Autodesk Fusion 360 part; units mm, degrees
(part 3 of 3)
  spline S132 degree 3 poles (44.3046, -6.0249) (44.0782, -5.7263) (43.6074, -5.1055) (43.5551, -4.3265) (43.528, -3.9222) knots 0 0 0 0 0.109936 0.228563 0.228563 0.228563 0.228563
  spline S133 degree 3 poles (43.528, -3.9222) (43.5425, -3.6461) (43.5714, -3.0995) (43.7867, -2.5965) (43.8932, -2.3475) knots 0 0 0 0 0.082236 0.16278 0.16278 0.16278 0.16278
  spline S134 degree 3 poles (43.8932, -2.3475) (44.0238, -2.1208) (44.2792, -1.6775) (44.6942, -1.3791) (44.897, -1.2333) knots 0 0 0 0 0.077495 0.151511 0.151511 0.151511 0.151511
  spline S135 degree 3 poles (44.897, -1.2333) (45.1198, -1.1205) (45.5753, -0.8899) (46.0853, -0.8612) (46.3458, -0.8465) knots 0 0 0 0 0.074062 0.151408 0.151408 0.151408 0.151408
  spline S136 degree 3 poles (46.3458, -0.8465) (46.7837, -0.8873) (47.6516, -0.9682) (48.2851, -1.5662) (48.5989, -1.8626) knots 0 0 0 0 0.127939 0.253596 0.253596 0.253596 0.253596
  spline S137 degree 3 poles (48.5989, -1.8626) (48.8518, -2.3009) (49.4454, -3.3299) (49.4615, -4.5253) (49.4707, -5.2115) knots 0 0 0 0 0.149571 0.35112 0.35112 0.35112 0.35112
  spline S138 degree 3 poles (49.4707, -5.2115) (49.459, -5.9817) (49.4386, -7.3304) (48.7865, -8.5026) (48.5068, -9.0055) knots 0 0 0 0 0.226592 0.396798 0.396798 0.396798 0.396798
  spline S139 degree 3 poles (48.5068, -9.0055) (48.1977, -9.3062) (47.5669, -9.9199) (46.689, -9.9973) (46.2415, -10.0368) knots 0 0 0 0 0.12539 0.255812 0.255812 0.255812 0.255812
  spline S140 degree 3 poles (53.719, -0.8465) (54.049, -0.866) (54.6793, -0.9032) (55.1973, -1.2619) (55.4441, -1.4328) knots 0 0 0 0 0.097038 0.185349 0.185349 0.185349 0.185349
  spline S141 degree 3 poles (55.4441, -1.4328) (55.6458, -1.6563) (56.0709, -2.1273) (56.1872, -2.7526) (56.2483, -3.0812) knots 0 0 0 0 0.088559 0.186622 0.186622 0.186622 0.186622
  line L73 (56.2483, -3.0812) -> (55.1862, -3.1794)
  spline S142 degree 3 poles (55.1862, -3.1794) (55.1392, -2.9549) (55.0543, -2.5494) (54.7889, -2.2336) (54.6705, -2.0928) knots 0 0 0 0 0.067535 0.121935 0.121935 0.121935 0.121935
  spline S143 degree 3 poles (54.6705, -2.0928) (54.5307, -1.9943) (54.2385, -1.7886) (53.8809, -1.7666) (53.6944, -1.7551) knots 0 0 0 0 0.050278 0.10511 0.10511 0.10511 0.10511
  spline S144 degree 3 poles (53.6944, -1.7551) (53.5321, -1.7635) (53.218, -1.7796) (52.937, -1.9204) (52.8012, -1.9884) knots 0 0 0 0 0.048163 0.093215 0.093215 0.093215 0.093215
  spline S145 degree 3 poles (52.8012, -1.9884) (52.6787, -2.0731) (52.4323, -2.2437) (52.2591, -2.4884) (52.1719, -2.6115) knots 0 0 0 0 0.044287 0.089169 0.089169 0.089169 0.089169
  spline S146 degree 3 poles (52.1719, -2.6115) (52.0912, -2.762) (51.912, -3.0962) (51.8143, -3.4629) (51.7606, -3.6644) knots 0 0 0 0 0.051067 0.113373 0.113373 0.113373 0.113373
  spline S147 degree 3 poles (51.7606, -3.6644) (51.7122, -3.8866) (51.6154, -4.3317) (51.6017, -4.787) (51.5948, -5.015) knots 0 0 0 0 0.068062 0.136332 0.136332 0.136332 0.136332
  spline S148 degree 3 poles (51.5948, -5.015) (51.5952, -5.0457) (51.5961, -5.1194) (51.5992, -5.193) (51.601, -5.236) knots 0 0 0 0 0.00921 0.02211 0.02211 0.02211 0.02211
  spline S149 degree 3 poles (51.601, -5.236) (51.723, -5.0675) (51.9709, -4.7253) (52.3261, -4.496) (52.5065, -4.3796) knots 0 0 0 0 0.061834 0.125606 0.125606 0.125606 0.125606
  spline S150 degree 3 poles (52.5065, -4.3796) (52.7021, -4.2838) (53.0946, -4.0916) (53.5309, -4.0647) (53.7497, -4.0512) knots 0 0 0 0 0.064656 0.129715 0.129715 0.129715 0.129715
  spline S151 degree 3 poles (53.7497, -4.0512) (54.1079, -4.085) (54.8248, -4.1528) (55.3685, -4.6252) (55.6405, -4.8615) knots 0 0 0 0 0.105109 0.210375 0.210375 0.210375 0.210375
  spline S152 degree 3 poles (55.6405, -4.8615) (55.866, -5.1627) (56.3391, -5.7946) (56.3883, -6.5845) (56.4141, -6.998) knots 0 0 0 0 0.110401 0.231667 0.231667 0.231667 0.231667
  spline S153 degree 3 poles (56.4141, -6.998) (56.387, -7.425) (56.3353, -8.2415) (55.8421, -8.8917) (55.6068, -9.2019) knots 0 0 0 0 0.125188 0.239403 0.239403 0.239403 0.239403
  spline S154 degree 3 poles (55.6068, -9.2019) (55.3181, -9.4454) (54.7333, -9.9388) (53.9703, -10.0039) (53.5839, -10.0368) knots 0 0 0 0 0.110411 0.223699 0.223699 0.223699 0.223699
  spline S155 degree 3 poles (53.5839, -10.0368) (53.2979, -10.0174) (52.7278, -9.9786) (52.2277, -9.702) (51.9785, -9.5641) knots 0 0 0 0 0.084857 0.169181 0.169181 0.169181 0.169181
  spline S156 degree 3 poles (51.9785, -9.5641) (51.7491, -9.3863) (51.2786, -9.0216) (51.0107, -8.4893) (50.8735, -8.2166) knots 0 0 0 0 0.08592 0.176242 0.176242 0.176242 0.176242
  spline S157 degree 3 poles (50.8735, -8.2166) (50.7639, -7.8622) (50.5093, -7.0391) (50.5008, -6.1758) (50.4959, -5.6842) knots 0 0 0 0 0.110733 0.257226 0.257226 0.257226 0.257226
  spline S158 degree 3 poles (50.4959, -5.6842) (50.5029, -5.1642) (50.5154, -4.232) (50.7615, -3.334) (50.8704, -2.9369) knots 0 0 0 0 0.155219 0.278258 0.278258 0.278258 0.278258
  spline S159 degree 3 poles (50.8704, -2.9369) (51.0041, -2.6212) (51.2596, -2.0182) (51.7507, -1.5864) (51.9847, -1.3806) knots 0 0 0 0 0.101354 0.193602 0.193602 0.193602 0.193602
  spline S160 degree 3 poles (51.9847, -1.3806) (52.2455, -1.2249) (52.7797, -0.906) (53.4011, -0.8666) (53.719, -0.8465) knots 0 0 0 0 0.089778 0.183816 0.183816 0.183816 0.183816
  spline S161 degree 3 poles (61.5464, -2.6606) (61.6352, -2.5633) (61.8062, -2.3758) (61.9458, -2.164) (62.013, -2.0621) knots 0 0 0 0 0.039446 0.075997 0.075997 0.075997 0.075997
  line L74 (62.013, -2.0621) -> (57.5989, -2.0621)
  line L75 (57.5989, -2.0621) -> (57.5989, -1)
  line L76 (57.5989, -1) -> (63.5477, -1)
  spline S162 degree 3 poles (63.5477, -1) (63.5455, -1.1315) (63.5411, -1.3938) (63.4595, -1.6431) (63.4188, -1.7674) knots 0 0 0 0 0.039224 0.078207 0.078207 0.078207 0.078207
  spline S163 degree 3 poles (63.4188, -1.7674) (63.3283, -1.9732) (63.1387, -2.4042) (62.8448, -2.7723) (62.6913, -2.9645) knots 0 0 0 0 0.067164 0.140612 0.140612 0.140612 0.140612
  spline S164 degree 3 poles (62.6913, -2.9645) (62.4914, -3.1804) (62.0405, -3.6673) (61.5298, -4.0914) (61.2456, -4.3274) knots 0 0 0 0 0.088193 0.198876 0.198876 0.198876 0.198876
  spline S165 degree 3 poles (61.2456, -4.3274) (60.823, -4.6738) (60.1112, -5.2575) (59.5078, -5.9515) (59.2626, -6.2336) knots 0 0 0 0 0.163519 0.275478 0.275478 0.275478 0.275478
  spline S166 degree 3 poles (59.2626, -6.2336) (59.1126, -6.4537) (58.8368, -6.8581) (58.7751, -7.3421) (58.7469, -7.5628) knots 0 0 0 0 0.078556 0.144369 0.144369 0.144369 0.144369
  spline S167 degree 3 poles (58.7469, -7.5628) (58.7663, -7.773) (58.805, -8.1924) (59.0796, -8.5116) (59.2166, -8.6709) knots 0 0 0 0 0.061675 0.123053 0.123053 0.123053 0.123053
  spline S168 degree 3 poles (59.2166, -8.6709) (59.3898, -8.8024) (59.7512, -9.0768) (60.2051, -9.1066) (60.4413, -9.1221) knots 0 0 0 0 0.063814 0.133113 0.133113 0.133113 0.133113
  spline S169 degree 3 poles (60.4413, -9.1221) (60.69, -9.1061) (61.1654, -9.0755) (61.5397, -8.7828) (61.7183, -8.6432) knots 0 0 0 0 0.072819 0.139233 0.139233 0.139233 0.139233
  spline S170 degree 3 poles (61.7183, -8.6432) (61.8581, -8.4604) (62.1564, -8.0703) (62.187, -7.5785) (62.2033, -7.3172) knots 0 0 0 0 0.067532 0.14406 0.14406 0.14406 0.14406
  line L77 (62.2033, -7.3172) -> (63.339, -7.4338)
  spline S171 degree 3 poles (63.339, -7.4338) (63.2823, -7.8239) (63.1758, -8.5568) (62.6889, -9.1113) (62.4611, -9.3707) knots 0 0 0 0 0.115358 0.216751 0.216751 0.216751 0.216751
  spline S172 degree 3 poles (62.4611, -9.3707) (62.1732, -9.5648) (61.5573, -9.98) (60.8131, -10.0171) (60.4168, -10.0368) knots 0 0 0 0 0.102212 0.218671 0.218671 0.218671 0.218671
  spline S173 degree 3 poles (60.4168, -10.0368) (60.0162, -10.0148) (59.2608, -9.9733) (58.6522, -9.5278) (58.3663, -9.3186) knots 0 0 0 0 0.117411 0.221461 0.221461 0.221461 0.221461
  spline S174 degree 3 poles (58.3663, -9.3186) (58.1461, -9.0639) (57.7032, -8.5517) (57.642, -7.8773) (57.6112, -7.5382) knots 0 0 0 0 0.098363 0.197784 0.197784 0.197784 0.197784
  spline S175 degree 3 poles (57.6112, -7.5382) (57.6208, -7.3578) (57.6404, -6.9926) (57.7677, -6.6497) (57.8322, -6.4761) knots 0 0 0 0 0.053848 0.109039 0.109039 0.109039 0.109039
  spline S176 degree 3 poles (57.8322, -6.4761) (57.9239, -6.2934) (58.1227, -5.8971) (58.4106, -5.5593) (58.5658, -5.3772) knots 0 0 0 0 0.061098 0.132556 0.132556 0.132556 0.132556
  spline S177 degree 3 poles (58.5658, -5.3772) (58.7902, -5.1459) (59.3307, -4.5887) (59.9231, -4.0868) (60.2694, -3.7933) knots 0 0 0 0 0.096642 0.232736 0.232736 0.232736 0.232736
  spline S178 degree 3 poles (60.2694, -3.7933) (60.545, -3.5635) (60.9822, -3.1988) (61.3941, -2.8059) (61.5464, -2.6606) knots 0 0 0 0 0.10759 0.17073 0.17073 0.17073 0.17073
  line L78 (-45.6235, -2.0621) -> (-45.6235, -1)
  line L79 (-45.6235, -1) -> (-40, -1)
  line L80 (-40, -1) -> (-40, -10)
  line L81 (-40, -10) -> (-41.191, -10)
  line L82 (-41.191, -10) -> (-41.191, -2.0621)
  line L83 (-41.191, -2.0621) -> (-45.6235, -2.0621)
  line L84 (-69.1487, -8.0723) -> (-69.1487, -1)
  line L85 (-69.1487, -1) -> (-68.0068, -1)
  line L86 (-68.0068, -1) -> (-68.0068, -10)
  line L87 (-68.0068, -10) -> (-69.2285, -10)
  line L88 (-69.2285, -10) -> (-73.9557, -2.9338)
  line L89 (-73.9557, -2.9338) -> (-73.9557, -10)
  line L90 (-73.9557, -10) -> (-75.0975, -10)
  line L91 (-75.0975, -10) -> (-75.0975, -1)
  line L92 (-75.0975, -1) -> (-73.8759, -1)
  line L93 (-73.8759, -1) -> (-69.1487, -8.0723)
  spline S179 degree 3 poles (-60.5662, -3.603) (-60.5811, -3.8787) (-60.6096, -4.4061) (-60.8815, -4.8578) (-61.0113, -5.0733) knots 0 0 0 0 0.081417 0.155718 0.155718 0.155718 0.155718
  spline S180 degree 3 poles (-61.0113, -5.0733) (-61.1801, -5.2563) (-61.531, -5.6364) (-62.0235, -5.7972) (-62.279, -5.8806) knots 0 0 0 0 0.073422 0.152542 0.152542 0.152542 0.152542
  spline S181 degree 3 poles (-62.279, -5.8806) (-62.0689, -5.9678) (-61.6746, -6.1313) (-61.3919, -6.45) (-61.2599, -6.5989) knots 0 0 0 0 0.067199 0.126131 0.126131 0.126131 0.126131
  spline S182 degree 3 poles (-61.2599, -6.5989) (-61.1632, -6.7656) (-60.963, -7.1109) (-60.9402, -7.5099) (-60.9284, -7.7162) knots 0 0 0 0 0.056974 0.118009 0.118009 0.118009 0.118009
  spline S183 degree 3 poles (-60.9284, -7.7162) (-60.9575, -8.0303) (-61.0155, -8.6567) (-61.4285, -9.1311) (-61.6344, -9.3677) knots 0 0 0 0 0.092106 0.183705 0.183705 0.183705 0.183705
  spline S184 degree 3 poles (-61.6344, -9.3677) (-61.8984, -9.5627) (-62.4553, -9.9741) (-63.1484, -10.0152) (-63.513, -10.0368) knots 0 0 0 0 0.096365 0.203276 0.203276 0.203276 0.203276
  spline S185 degree 3 poles (-63.513, -10.0368) (-63.8803, -10.0142) (-64.5813, -9.971) (-65.1427, -9.5518) (-65.41, -9.3523) knots 0 0 0 0 0.107729 0.205612 0.205612 0.205612 0.205612
  spline S186 degree 3 poles (-65.41, -9.3523) (-65.6195, -9.1122) (-66.0373, -8.6334) (-66.098, -8.0009) (-66.1282, -7.6855) knots 0 0 0 0 0.093071 0.185613 0.185613 0.185613 0.185613
  spline S187 degree 3 poles (-66.1282, -7.6855) (-66.116, -7.4857) (-66.0923, -7.0963) (-65.8956, -6.7597) (-65.7998, -6.5958) knots 0 0 0 0 0.059125 0.115239 0.115239 0.115239 0.115239
  spline S188 degree 3 poles (-65.7998, -6.5958) (-65.67, -6.448) (-65.3935, -6.1329) (-65.0071, -5.9681) (-64.8022, -5.8806) knots 0 0 0 0 0.058279 0.124147 0.124147 0.124147 0.124147
  spline S189 degree 3 poles (-64.8022, -5.8806) (-65.0584, -5.7815) (-65.5496, -5.5915) (-65.8974, -5.1973) (-66.0638, -5.0089) knots 0 0 0 0 0.081068 0.15536 0.15536 0.15536 0.15536
  spline S190 degree 3 poles (-66.0638, -5.0089) (-66.19, -4.7944) (-66.4507, -4.3513) (-66.481, -3.8375) (-66.4966, -3.5723) knots 0 0 0 0 0.073547 0.151957 0.151957 0.151957 0.151957
  spline S191 degree 3 poles (-66.4966, -3.5723) (-66.4633, -3.2036) (-66.397, -2.47) (-65.9182, -1.9106) (-65.6801, -1.6323) knots 0 0 0 0 0.108151 0.215189 0.215189 0.215189 0.215189
  spline S192 degree 3 poles (-65.6801, -1.6323) (-65.3772, -1.4033) (-64.7429, -0.9235) (-63.9472, -0.8729) (-63.5314, -0.8465) knots 0 0 0 0 0.111408 0.233329 0.233329 0.233329 0.233329
  spline S193 degree 3 poles (-63.5314, -0.8465) (-63.1155, -0.8731) (-62.3193, -0.9241) (-61.6855, -1.4054) (-61.3827, -1.6354) knots 0 0 0 0 0.121933 0.233463 0.233463 0.233463 0.233463
  spline S194 degree 3 poles (-61.3827, -1.6354) (-61.1445, -1.9166) (-60.6632, -2.4851) (-60.5987, -3.2278) (-60.5662, -3.603) knots 0 0 0 0 0.107732 0.217767 0.217767 0.217767 0.217767
  spline S195 degree 3 poles (-56.281, -0.8465) (-55.951, -0.866) (-55.3207, -0.9032) (-54.8027, -1.2619) (-54.5559, -1.4328) knots 0 0 0 0 0.097038 0.185349 0.185349 0.185349 0.185349
  spline S196 degree 3 poles (-54.5559, -1.4328) (-54.3542, -1.6563) (-53.9291, -2.1273) (-53.8128, -2.7526) (-53.7517, -3.0812) knots 0 0 0 0 0.088559 0.186622 0.186622 0.186622 0.186622
  line L94 (-53.7517, -3.0812) -> (-54.8138, -3.1794)
  spline S197 degree 3 poles (-54.8138, -3.1794) (-54.8608, -2.9549) (-54.9457, -2.5494) (-55.2111, -2.2336) (-55.3295, -2.0928) knots 0 0 0 0 0.067535 0.121935 0.121935 0.121935 0.121935
  spline S198 degree 3 poles (-55.3295, -2.0928) (-55.4693, -1.9943) (-55.7615, -1.7886) (-56.1191, -1.7666) (-56.3056, -1.7551) knots 0 0 0 0 0.050278 0.10511 0.10511 0.10511 0.10511
  spline S199 degree 3 poles (-56.3056, -1.7551) (-56.4679, -1.7635) (-56.782, -1.7796) (-57.063, -1.9204) (-57.1988, -1.9884) knots 0 0 0 0 0.048163 0.093215 0.093215 0.093215 0.093215
  spline S200 degree 3 poles (-57.1988, -1.9884) (-57.3213, -2.0731) (-57.5677, -2.2437) (-57.7409, -2.4884) (-57.8281, -2.6115) knots 0 0 0 0 0.044287 0.089169 0.089169 0.089169 0.089169
  spline S201 degree 3 poles (-57.8281, -2.6115) (-57.9088, -2.762) (-58.088, -3.0962) (-58.1857, -3.4629) (-58.2394, -3.6644) knots 0 0 0 0 0.051067 0.113373 0.113373 0.113373 0.113373
  spline S202 degree 3 poles (-58.2394, -3.6644) (-58.2878, -3.8866) (-58.3846, -4.3317) (-58.3983, -4.787) (-58.4052, -5.015) knots 0 0 0 0 0.068062 0.136332 0.136332 0.136332 0.136332
  spline S203 degree 3 poles (-58.4052, -5.015) (-58.4048, -5.0457) (-58.4039, -5.1194) (-58.4008, -5.193) (-58.399, -5.236) knots 0 0 0 0 0.00921 0.02211 0.02211 0.02211 0.02211
  spline S204 degree 3 poles (-58.399, -5.236) (-58.277, -5.0675) (-58.0291, -4.7253) (-57.6739, -4.496) (-57.4935, -4.3796) knots 0 0 0 0 0.061834 0.125606 0.125606 0.125606 0.125606
  spline S205 degree 3 poles (-57.4935, -4.3796) (-57.2979, -4.2838) (-56.9054, -4.0916) (-56.4691, -4.0647) (-56.2503, -4.0512) knots 0 0 0 0 0.064656 0.129715 0.129715 0.129715 0.129715
  spline S206 degree 3 poles (-56.2503, -4.0512) (-55.8921, -4.085) (-55.1752, -4.1528) (-54.6315, -4.6252) (-54.3595, -4.8615) knots 0 0 0 0 0.105109 0.210375 0.210375 0.210375 0.210375
  spline S207 degree 3 poles (-54.3595, -4.8615) (-54.134, -5.1627) (-53.6609, -5.7946) (-53.6117, -6.5845) (-53.5859, -6.998) knots 0 0 0 0 0.110401 0.231667 0.231667 0.231667 0.231667
  spline S208 degree 3 poles (-53.5859, -6.998) (-53.613, -7.425) (-53.6647, -8.2415) (-54.1579, -8.8917) (-54.3932, -9.2019) knots 0 0 0 0 0.125188 0.239403 0.239403 0.239403 0.239403
  spline S209 degree 3 poles (-54.3932, -9.2019) (-54.6819, -9.4454) (-55.2667, -9.9388) (-56.0297, -10.0039) (-56.4161, -10.0368) knots 0 0 0 0 0.110411 0.223699 0.223699 0.223699 0.223699
  spline S210 degree 3 poles (-56.4161, -10.0368) (-56.7021, -10.0174) (-57.2722, -9.9786) (-57.7723, -9.702) (-58.0215, -9.5641) knots 0 0 0 0 0.084857 0.169181 0.169181 0.169181 0.169181
  spline S211 degree 3 poles (-58.0215, -9.5641) (-58.2509, -9.3863) (-58.7214, -9.0216) (-58.9893, -8.4893) (-59.1265, -8.2166) knots 0 0 0 0 0.08592 0.176242 0.176242 0.176242 0.176242
  spline S212 degree 3 poles (-59.1265, -8.2166) (-59.2361, -7.8622) (-59.4907, -7.0391) (-59.4992, -6.1758) (-59.5041, -5.6842) knots 0 0 0 0 0.110733 0.257226 0.257226 0.257226 0.257226
  spline S213 degree 3 poles (-59.5041, -5.6842) (-59.4971, -5.1642) (-59.4846, -4.232) (-59.2385, -3.334) (-59.1296, -2.9369) knots 0 0 0 0 0.155219 0.278258 0.278258 0.278258 0.278258
  spline S214 degree 3 poles (-59.1296, -2.9369) (-58.9959, -2.6212) (-58.7404, -2.0182) (-58.2493, -1.5864) (-58.0153, -1.3806) knots 0 0 0 0 0.101354 0.193602 0.193602 0.193602 0.193602
  spline S215 degree 3 poles (-58.0153, -1.3806) (-57.7545, -1.2249) (-57.2203, -0.906) (-56.5989, -0.8666) (-56.281, -0.8465) knots 0 0 0 0 0.089778 0.183816 0.183816 0.183816 0.183816
  spline S216 degree 3 poles (-48.4536, -2.6606) (-48.3648, -2.5633) (-48.1938, -2.3758) (-48.0542, -2.164) (-47.987, -2.0621) knots 0 0 0 0 0.039446 0.075997 0.075997 0.075997 0.075997
  line L95 (-47.987, -2.0621) -> (-52.4011, -2.0621)
  line L96 (-52.4011, -2.0621) -> (-52.4011, -1)
  line L97 (-52.4011, -1) -> (-46.4523, -1)
  spline S217 degree 3 poles (-46.4523, -1) (-46.4545, -1.1315) (-46.4589, -1.3938) (-46.5405, -1.6431) (-46.5812, -1.7674) knots 0 0 0 0 0.039224 0.078207 0.078207 0.078207 0.078207
  spline S218 degree 3 poles (-46.5812, -1.7674) (-46.6717, -1.9732) (-46.8613, -2.4042) (-47.1552, -2.7723) (-47.3087, -2.9645) knots 0 0 0 0 0.067164 0.140612 0.140612 0.140612 0.140612
  spline S219 degree 3 poles (-47.3087, -2.9645) (-47.5086, -3.1804) (-47.9595, -3.6673) (-48.4702, -4.0914) (-48.7544, -4.3274) knots 0 0 0 0 0.088193 0.198876 0.198876 0.198876 0.198876
  spline S220 degree 3 poles (-48.7544, -4.3274) (-49.177, -4.6738) (-49.8888, -5.2575) (-50.4922, -5.9515) (-50.7374, -6.2336) knots 0 0 0 0 0.163519 0.275478 0.275478 0.275478 0.275478
  spline S221 degree 3 poles (-50.7374, -6.2336) (-50.8874, -6.4537) (-51.1632, -6.8581) (-51.2249, -7.3421) (-51.2531, -7.5628) knots 0 0 0 0 0.078556 0.144369 0.144369 0.144369 0.144369
  spline S222 degree 3 poles (-51.2531, -7.5628) (-51.2337, -7.773) (-51.195, -8.1924) (-50.9204, -8.5116) (-50.7834, -8.6709) knots 0 0 0 0 0.061675 0.123053 0.123053 0.123053 0.123053
  spline S223 degree 3 poles (-50.7834, -8.6709) (-50.6102, -8.8024) (-50.2488, -9.0768) (-49.7949, -9.1066) (-49.5587, -9.1221) knots 0 0 0 0 0.063814 0.133113 0.133113 0.133113 0.133113
  spline S224 degree 3 poles (-49.5587, -9.1221) (-49.31, -9.1061) (-48.8346, -9.0755) (-48.4603, -8.7828) (-48.2817, -8.6432) knots 0 0 0 0 0.072819 0.139233 0.139233 0.139233 0.139233
  spline S225 degree 3 poles (-48.2817, -8.6432) (-48.1419, -8.4604) (-47.8436, -8.0703) (-47.813, -7.5785) (-47.7967, -7.3172) knots 0 0 0 0 0.067532 0.14406 0.14406 0.14406 0.14406
  line L98 (-47.7967, -7.3172) -> (-46.661, -7.4338)
  spline S226 degree 3 poles (-46.661, -7.4338) (-46.7177, -7.8239) (-46.8242, -8.5568) (-47.3111, -9.1113) (-47.5389, -9.3707) knots 0 0 0 0 0.115358 0.216751 0.216751 0.216751 0.216751
  spline S227 degree 3 poles (-47.5389, -9.3707) (-47.8268, -9.5648) (-48.4427, -9.98) (-49.1869, -10.0171) (-49.5832, -10.0368) knots 0 0 0 0 0.102212 0.218671 0.218671 0.218671 0.218671
  spline S228 degree 3 poles (-49.5832, -10.0368) (-49.9838, -10.0148) (-50.7392, -9.9733) (-51.3478, -9.5278) (-51.6337, -9.3186) knots 0 0 0 0 0.117411 0.221461 0.221461 0.221461 0.221461
  spline S229 degree 3 poles (-51.6337, -9.3186) (-51.8539, -9.0639) (-52.2968, -8.5517) (-52.358, -7.8773) (-52.3888, -7.5382) knots 0 0 0 0 0.098363 0.197784 0.197784 0.197784 0.197784
  spline S230 degree 3 poles (-52.3888, -7.5382) (-52.3792, -7.3578) (-52.3596, -6.9926) (-52.2323, -6.6497) (-52.1678, -6.4761) knots 0 0 0 0 0.053848 0.109039 0.109039 0.109039 0.109039
  spline S231 degree 3 poles (-52.1678, -6.4761) (-52.0761, -6.2934) (-51.8773, -5.8971) (-51.5894, -5.5593) (-51.4342, -5.3772) knots 0 0 0 0 0.061098 0.132556 0.132556 0.132556 0.132556
  spline S232 degree 3 poles (-51.4342, -5.3772) (-51.2098, -5.1459) (-50.6693, -4.5887) (-50.0769, -4.0868) (-49.7306, -3.7933) knots 0 0 0 0 0.096642 0.232736 0.232736 0.232736 0.232736
  spline S233 degree 3 poles (-49.7306, -3.7933) (-49.455, -3.5635) (-49.0178, -3.1988) (-48.6059, -2.8059) (-48.4536, -2.6606) knots 0 0 0 0 0.10759 0.17073 0.17073 0.17073 0.17073
  line L99 (60, 40) -> (60, 85) construction
  line L100 (60, 85) -> (50, 85) construction
  line L101 (50, 85) -> (50, 40) construction
  line L102 (50, 40) -> (60, 40) construction
  dimension "d65" = 9
  text T0 "Arduino" font "Arial" height 9 align left top in box 45 x 10 at (60, 40) x (0, 1) y (-1, 0) spacing 1 kerned
extrude "Estrusione5" cut sketch "Schizzo5" against normal blind 1 text T0
fillet "Raccordo1" radius 3.5 1 edges at (100, -100, 1.5)
fillet "Raccordo2" radius 3.5 1 edges at (-100, -100, 1.5)
fillet "Raccordo3" radius 3.5 1 edges at (100, 100, 1.5)
fillet "Raccordo4" radius 3.5 1 edges at (-100, 100, 1.5)
equation "d50 = 'Raspberry'"
equation "d54 = 'L296N'"
equation "d56 = 'L298N'"
equation "d58 = 'ARDUINO'"
equation "d62 = 'L298N'"
equation "d66 = 'Arduino'"
